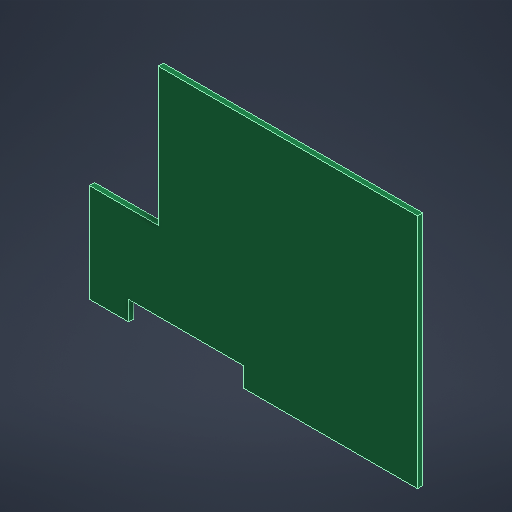
# Autodesk Inventor part: ref_pcb
Saved by Autodesk Inventor 2027.1 (Build 311270010, 270A)
## iProperties
Created: 2026-10-22
Part Number: ref_pcb
Material: 일반
Document SubType Name: Modeling
Designer: sungjun
Density: 1 g/cm^3
Appearance: ref_pcb_c
Author: sungjun
Autodesk Inventor part; units mm, degrees
ref_plane "작업 평면1" through (0, 0, 7.3) normal (0, 0, 1) x (1, 0, 0)
sketch "스케치1" plane through (0, 0, 7.3) normal (0, 0, 1) x (1, 0, 0)
  line L0 (3.5, 3.5) -> (103.5, 3.5)
  line L1 (103.5, 3.5) -> (103.5, 75.5)
  line L2 (103.5, 75.5) -> (3.5, 75.5)
  line L3 (3.5, 75.5) -> (3.5, 3.5)
  constraints: 8 end point, 2 parallel, 1 horizontal, 1 perpendicular
extrude "돌출1" add sketch "스케치1" along normal mid plane 1.6
ref_plane "작업 평면2" through (0, 0, 7.3) normal (0, 0, 1) x (1, 0, 0)
sketch "스케치2" plane through (0, 0, 7.3) normal (0, 0, 1) x (1, 0, 0)
  line L0 (2.5, 33.5) -> (24.5, 33.5)
  line L1 (24.5, 33.5) -> (24.5, 76.5)
  line L2 (24.5, 76.5) -> (2.5, 76.5)
  line L3 (2.5, 76.5) -> (2.5, 33.5)
  constraints: 8 end point, 2 parallel, 1 horizontal, 1 perpendicular
extrude "돌출2" cut sketch "스케치2" along normal mid plane 3.6
ref_plane "작업 평면3" through (0, 0, 7.3) normal (0, 0, 1) x (1, 0, 0)
sketch "스케치3" plane through (0, 0, 7.3) normal (0, 0, 1) x (1, 0, 0)
  line L0 (15.5, 2.5) -> (50.5, 2.5)
  line L1 (50.5, 2.5) -> (50.5, 9.45)
  line L2 (50.5, 9.45) -> (15.5, 9.45)
  line L3 (15.5, 9.45) -> (15.5, 2.5)
  constraints: 8 end point, 2 parallel, 1 horizontal, 1 perpendicular
extrude "돌출3" cut sketch "스케치3" along normal mid plane 3.6
